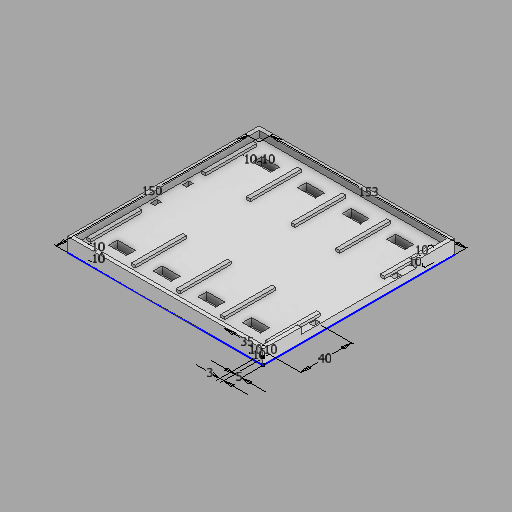
# Autodesk Inventor part: Part1
Saved by Autodesk Inventor 2027.1 (Build 311270010, 270A)
## iProperties
Created: 2026-11-08
Part Number: Part1
Material: Generic
Document SubType Name: Modeling
Designer: migue
Density: 1 g/cm^3
Appearance: Default
Author: migue
Autodesk Inventor part; units mm, degrees
ref_plane "YZ Plane" through (0, 0, 0) normal (1, 0, 0) x (0, 1, 0)
ref_plane "XZ Plane" through (0, 0, 0) normal (0, 1, 0) x (-1, 0, 0)
ref_plane "XY Plane" through (0, 0, 0) normal (0, 0, 1) x (1, 0, 0)
sketch "Sketch1" plane through (0, 0, 0) normal (0, 1, 0) x (-1, 0, 0)
  line L0 (0, 0) -> (153, 0)
  line L1 (153, 0) -> (153, -150)
  line L2 (153, -150) -> (0, -150)
  line L3 (0, -150) -> (0, 0)
  line L4 (5, -10) -> (8, -10)
  line L5 (8, -10) -> (8, -50)
  line L6 (8, -50) -> (5, -50)
  line L7 (5, -50) -> (5, -10)
  line L8 (40, -50) -> (40, -10)
  line L9 (43, -10) -> (43, -50)
  line L10 (43, -50) -> (40, -50)
  line L11 (40, -10) -> (43, -10)
  line L12 (75, -50) -> (75, -10)
  line L13 (78, -10) -> (78, -50)
  line L14 (78, -50) -> (75, -50)
  line L15 (75, -10) -> (78, -10)
  line L16 (110, -50) -> (110, -10)
  line L17 (113, -10) -> (113, -50)
  line L18 (113, -50) -> (110, -50)
  line L19 (110, -10) -> (113, -10)
  line L20 (145, -50) -> (145, -10)
  line L21 (148, -10) -> (148, -50)
  line L22 (148, -50) -> (145, -50)
  line L23 (145, -10) -> (148, -10)
  line L24 (0, -75) -> (153, -75) construction
  line L25 (5, -140) -> (8, -140)
  line L26 (8, -140) -> (8, -100)
  line L27 (8, -100) -> (5, -100)
  line L28 (5, -100) -> (5, -140)
  line L29 (40, -100) -> (40, -140)
  line L30 (43, -140) -> (43, -100)
  line L31 (43, -100) -> (40, -100)
  line L32 (40, -140) -> (43, -140)
  line L33 (75, -100) -> (75, -140)
  line L34 (78, -140) -> (78, -100)
  line L35 (78, -100) -> (75, -100)
  line L36 (75, -140) -> (78, -140)
  line L37 (110, -100) -> (110, -140)
  line L38 (113, -140) -> (113, -100)
  line L39 (113, -100) -> (110, -100)
  line L40 (110, -140) -> (113, -140)
  line L41 (145, -100) -> (145, -140)
  line L42 (148, -140) -> (148, -100)
  line L43 (148, -100) -> (145, -100)
  line L44 (145, -140) -> (148, -140)
  dimension "d0" = 153
  dimension "d1" = 150
  dimension "d2" = 10
  dimension "d3" = 5
  dimension "d4" = 3
  dimension "d5" = 40
  dimension "d11" = 35
  constraints: 90 end point, 20 symmetric about line, 4 parallel, 3 horizontal, 2 midpoint, 2 perpendicular, 32 other
  measures "d0" distance of L1.end L2.end
  measures "d1" distance of L0.end L1.end
  measures "d2" distance from line of L0 L4.start
  measures "d3" distance between parallel lines of L3 L7
  measures "d4" distance between parallel lines of L5 L7
  measures "d5" distance of L6.end L4.start
  measures "d11" distance of L4.start L8.end
extrude "Extrusion1" add sketch "Sketch1" along normal blind 6
extrude "Extrusion2" add sketch "Sketch1" along normal blind 8 contours L4 L5 L6 L7 | L8 L11 L9 L10 | L12 L15 L13 L14 | L16 L19 L17 L18 | L20 L23 L21 L22 | L28 L27 L26 L25 | L31 L30 L32 L29 | L35 L34 L36 L33 | L39 L38 L40 L37 | L43 L42 L44 L41
sketch "Sketch3" plane through (0, 6, 0) normal (0, 1, 0) x (1, 0, 0)
  line L0 (-17, 15) -> (-31, 15)
  line L1 (-31, 15) -> (-31, 22)
  line L2 (-31, 22) -> (-17, 22)
  line L3 (-17, 22) -> (-17, 15)
  line L4 (-8, 50) -> (-8, 10) projected
  line L5 (-40, 10) -> (-40, 50) projected
  line L6 (-8, 10) -> (-40, 10) construction
  line L7 (-24, 10) -> (-24, 15) construction
  line L8 (-75, 10) -> (-75, 50) construction
  line L9 (-75, 10) -> (-43, 10) construction
  line L10 (-43, 50) -> (-43, 10) construction
  line L11 (-59, 10) -> (-59, 22) construction
  line L12 (-66, 15) -> (-66, 22)
  line L13 (-66, 22) -> (-52, 22)
  line L14 (-52, 22) -> (-52, 15)
  line L15 (-52, 15) -> (-66, 15)
  line L16 (-101, 15) -> (-101, 22)
  line L17 (-101, 22) -> (-87, 22)
  line L18 (-87, 22) -> (-87, 15)
  line L19 (-87, 15) -> (-101, 15)
  line L20 (-136, 15) -> (-136, 22)
  line L21 (-136, 22) -> (-122, 22)
  line L22 (-122, 22) -> (-122, 15)
  line L23 (-122, 15) -> (-136, 15)
  line L24 (-153, 150) -> (-153, 0) projected
  line L25 (-153, 75) -> (0, 75) construction
  line L26 (0, 0) -> (0, 150) projected
  line L27 (-17, 135) -> (-31, 135)
  line L28 (-31, 135) -> (-31, 128)
  line L29 (-31, 128) -> (-17, 128)
  line L30 (-17, 128) -> (-17, 135)
  line L31 (-66, 135) -> (-66, 128)
  line L32 (-66, 128) -> (-52, 128)
  line L33 (-52, 128) -> (-52, 135)
  line L34 (-52, 135) -> (-66, 135)
  line L35 (-101, 135) -> (-101, 128)
  line L36 (-101, 128) -> (-87, 128)
  line L37 (-87, 128) -> (-87, 135)
  line L38 (-87, 135) -> (-101, 135)
  line L39 (-136, 135) -> (-136, 128)
  line L40 (-136, 128) -> (-122, 128)
  line L41 (-122, 128) -> (-122, 135)
  line L42 (-122, 135) -> (-136, 135)
  point P0 (-24, 12.5)
  point P1 (-59, 15)
  point P2 (-94, 15)
  point P3 (-129, 15)
  point P4 (-24, 135)
  point P5 (-24, 137.5)
  point P6 (-59, 128)
  point P7 (-59, 135)
  point P8 (-94, 135)
  point P9 (-129, 135)
  dimension "d20" = 7
  dimension "d21" = 14
  dimension "d22" = 5
  dimension "d25" = 35
  constraints: 74 end point, 22 symmetric about line, 7 midpoint, 4 horizontal, 2 parallel, 2 vertical, 1 perpendicular, 27 other
  measures "d20" distance of L0.end L1.end
  measures "d21" distance of L1.end L2.end
  measures "d22" distance of L7.start L7.end
  measures "d25" distance of L1.end L12.end
extrude "Extrusion3" cut sketch "Sketch3" against normal through all
sketch "Sketch4" plane through (0, 6, 0) normal (0, 1, 0) x (1, 0, 0)
  point P0 (0, 0)
sketch "Sketch5" plane through (0, 6, 0) normal (0, 1, 0) x (1, 0, 0)
  line L0 (-153, 150) -> (-153, 0) projected
  line L1 (-153, 0) -> (0, 0) projected
  line L2 (0, 0) -> (0, 150) projected
  line L3 (0, 150) -> (-153, 150) projected
  line L4 (-150, 3) -> (-150, 147)
  line L5 (-150, 147) -> (-3, 147)
  line L6 (-3, 3) -> (-150, 3)
  line L7 (-3, 30) -> (0, 30)
  line L8 (-3, 120) -> (0, 120)
  line L9 (-8, 100) -> (-5, 100) projected
  line L10 (-5, 50) -> (-8, 50) projected
  line L11 (-3, 147) -> (-3, 120)
  line L12 (-3, 30) -> (-3, 3)
  point P0 (-1.5, 30)
  point P1 (-6.5, 50)
  point P2 (-6.5, 100)
  point P3 (-1.5, 120)
  dimension "d32" = 3
  dimension "d36" = 20
  dimension "d37" = 20
  constraints: 14 end point, 4 midpoint, 2 perpendicular, 2 point on line, 1 other
  measures "d32" distance between parallel lines of L0 L4
  measures "d36" vertical distance of point (-1.5, 30) point (-6.5, 50)
  measures "d37" vertical distance of point (-6.5, 100) point (-1.5, 120)
extrude "Extrusion4" add sketch "Sketch5" along normal blind 5 contours L3 L2 L8 L11 L5 L4 L6 L12 L7 L1 L0
sketch "Sketch6" plane through (0, 6, 0) normal (0, 1, 0) x (1, 0, 0)
  line L0 (-148, 60) -> (-144.8, 60)
  line L1 (-144.8, 60) -> (-144.8, 65)
  line L2 (-144.8, 65) -> (-148, 65)
  line L3 (-148, 65) -> (-148, 60)
  line L4 (-148, 90) -> (-144.8, 90)
  line L5 (-144.8, 90) -> (-144.8, 85)
  line L6 (-144.8, 85) -> (-148, 85)
  line L7 (-148, 85) -> (-148, 90)
  line L8 (-148, 140) -> (-148, 100) projected
  line L9 (-148, 50) -> (-148, 10) projected
  line L10 (-145, 50) -> (-148, 50) projected
  line L11 (-148, 100) -> (-145, 100) projected
  line L12 (-4.2659, 109.3554) -> (-1.0659, 109.3554)
  line L13 (-1.0659, 109.3554) -> (-1.0659, 104.3554)
  line L14 (-1.0659, 104.3554) -> (-4.2659, 104.3554)
  line L15 (-4.2659, 104.3554) -> (-4.2659, 109.3554)
  line L16 (-153, 150) -> (-153, 0) construction
  line L17 (-153, 75) -> (0, 75) construction
  line L18 (0, 30) -> (0, 120) construction
  line L19 (-1.0659, 109.3554) -> (-4.2659, 104.3554) construction
  line L20 (-4.2659, 109.3554) -> (-1.0659, 104.3554) construction
  line L21 (-144.8, 90) -> (-148, 85) construction
  line L22 (-148, 90) -> (-144.8, 85) construction
  line L23 (-144.8, 65) -> (-148, 60) construction
  line L24 (-144.8, 60) -> (-148, 65) construction
  line L25 (-4.2659, 40.6446) -> (-1.0659, 40.6446)
  line L26 (-1.0659, 40.6446) -> (-1.0659, 45.6446)
  line L27 (-1.0659, 45.6446) -> (-4.2659, 45.6446)
  line L28 (-4.2659, 45.6446) -> (-4.2659, 40.6446)
  line L29 (-1.0659, 40.6446) -> (-4.2659, 45.6446) construction
  line L30 (-4.2659, 40.6446) -> (-1.0659, 45.6446) construction
  point P0 (0, 0)
  point P1 (-146.4, 85)
  point P2 (-146.4, 65)
  point P3 (-2.6659, 106.8554)
  point P4 (-146.4, 87.5)
  point P5 (-146.4, 87.5)
  point P6 (-146.4, 62.5)
  point P7 (-2.6659, 43.1446)
  dimension "d38" = 3.2
  dimension "d39" = 5
  dimension "d40" = 5
  dimension "d41" = 5
  dimension "d44" = 31.8554
  dimension "d46" = 12.5
  dimension "d47" = 12.5
  dimension "d48" = 140.5341
  dimension "d49" = 3.2
  constraints: 50 end point, 8 midpoint, 6 parallel, 5 symmetric about line, 3 horizontal, 3 perpendicular, 2 collinear, 2 point on line
  measures "d38" distance of L13.end L14.end
  measures "d39" distance of L12.end L13.end
  measures "d40" distance of L0.end L1.end
  measures "d41" distance of L4.end L5.end
  measures "d44" distance from line of L17 point (-2.666, 106.855)
  measures "d46" distance from line of L17 point (-146.4, 87.5)
  measures "d47" distance from line of L17 point (-146.4, 62.5)
  measures "d48" horizontal distance of L4.end L14.end
  measures "d49" distance of L5.end L6.end
extrude "Extrusion5" cut sketch "Sketch6" against normal through all
sketch "Sketch7" plane through (0, 0, 0) normal (0, -1, 0) x (1, 0, 0)
  line L0 (-3, -147) -> (-150, -147) projected
  line L1 (-3, -147) -> (-13, -147)
  line L2 (-13, -147) -> (-13, -137)
  line L3 (-13, -137) -> (-3, -137)
  line L4 (-3, -137) -> (-3, -147)
  line L5 (-150, -147) -> (-140, -147)
  line L6 (-140, -147) -> (-140, -137)
  line L7 (-140, -137) -> (-150, -137)
  line L8 (-150, -137) -> (-150, -147)
  line L9 (-150, -3) -> (-3, -3) projected
  line L10 (-150, -3) -> (-140, -3)
  line L11 (-140, -3) -> (-140, -13)
  line L12 (-140, -13) -> (-150, -13)
  line L13 (-150, -13) -> (-150, -3)
  line L14 (-3, -3) -> (-13, -3)
  line L15 (-13, -3) -> (-13, -13)
  line L16 (-13, -13) -> (-3, -13)
  line L17 (-3, -13) -> (-3, -3)
  point P0 (0, 0)
  dimension "d50" = 10
  dimension "d51" = 10
  dimension "d52" = 10
  dimension "d53" = 10
  dimension "d54" = 10
  dimension "d55" = 10
  dimension "d56" = 10
  dimension "d57" = 10
  constraints: 32 end point, 8 parallel, 4 horizontal, 4 perpendicular
  measures "d50" distance of L1.end L2.end
  measures "d51" distance of L2.end L3.end
  measures "d52" distance of L7.end L6.end
  measures "d53" distance of L6.end L5.end
  measures "d54" distance of L11.end L12.end
  measures "d55" distance of L10.end L11.end
  measures "d56" distance of L16.end L15.end
  measures "d57" distance of L15.end L14.end
body "Solid1"
